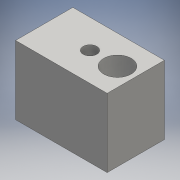
# Autodesk Inventor part: inventor_parameter_expressions
Saved by Autodesk Inventor 2016 (Build 200138000, 138)
## iProperties
Created: 2026-11-22
Part Number: inventor_parameter_expressions
Checked By: Fixture Builder
Material: Generic
Document SubType Name: Modeling
Designer: Fixture Builder
Engineer: Fixture Builder
Density: 1 g/cm^3
Appearance: Default
Manager: Fixture Builder
Company: Fixture Builder
Author: Fixture Builder
Last Saved By: Fixture Builder
Autodesk Inventor part; units mm, degrees
ref_plane "YZ Plane" through (0, 0, 0) normal (1, 0, 0) x (0, 1, 0)
ref_plane "XZ Plane" through (0, 0, 0) normal (0, 1, 0) x (-1, 0, 0)
ref_plane "XY Plane" through (0, 0, 0) normal (0, 0, 1) x (1, 0, 0)
sketch "Sketch1" plane through (0, 0, 0) normal (0, 0, 1) x (1, 0, 0)
  line L0 (0, 0) -> (40, 0)
  line L1 (40, 0) -> (40, 25)
  line L2 (40, 25) -> (0, 25)
  line L3 (0, 25) -> (0, 0)
  circle A0 centre (20, 12.5) radius 3
  circle A1 centre (32, 12.5) radius 6
  dimension "d0" = 40
  dimension "d1" = 25
  dimension "d2" = 20
  dimension "d3" = 6
  dimension "d4" = 12
  constraints: 8 end point, 2 centre point, 2 parallel, 1 horizontal, 1 perpendicular, 1 other
  measures "d0" distance of L0.start L0.end
  measures "d1" distance of L0.end L1.end
  measures "d2" horizontal distance of L0.start A0.centre
  measures "d3" diameter of A0
  measures "d4" diameter of A1
extrude "Block" add sketch "Sketch1" along normal blind 30
equation "\"d0\" = Width"
equation "\"d2\" = Height"
equation "\"d3\" = Hole"
equation "\"d4\" = 2 * d3"
equation "\"d5\" = 1.5 * Height"
equation "\"Width\" = 40"
equation "\"Height\" = 0.5 * Width"
equation "\"Hole\" = 6"
body "Solid1"
